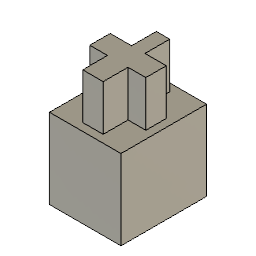
adapter_mitsumi_spacebar_to_cherry_stabilizer (Autodesk Fusion 360 design; units mm, degrees)
part number: 2025-08-30-15-09-30-402
Autodesk Fusion 360 part; units mm, degrees
note: some values were not read from the file. Set by a fixed rule: which face or edge a step refers to.
sketch "Mitsumi keycap interface" plane through (0, 0, 0) normal (0, 0, 1) x (1, 0, 0)
  line L0 (-0.48, 2.5) -> (0.48, 2.5)
  line L1 (0.48, 2.5) -> (0.48, 0.73)
  line L2 (-0.48, 0.7299) -> (-0.48, 2.5)
  line L3 (-2, 0.73) -> (2, 0.73)
  line L4 (2, 0.73) -> (2, -0.73)
  line L5 (2, -0.73) -> (-2, -0.73)
  line L6 (-2, -0.73) -> (-2, 0.73)
  line L7 (0.73, -0.73) -> (0.73, -2.5)
  line L8 (0.73, -2.5) -> (-0.73, -2.5)
  line L9 (-0.73, -2.5) -> (-0.73, -0.73)
  line L10 (0, 3.5) -> (0, -3.5) construction
  line L11 (-2.5, 0) -> (2.5, 0) construction
  dimension "d2" = 1.77
  dimension "d3" = 4
  dimension "d6" = 1.77
  dimension "d38" = 0.73
  dimension "d44" = 0.73
  dimension "d63" = 0.73
  dimension "d65" = 0.48
  dimension "d67" = 0.48
  dimension "d68" = 5
  dimension "d69" = 0.73
  constraint horizontal L3
  constraint coincident L5 L9.end
  constraint perpendicular L4 L5
  constraint coincident L5 L7.start
  constraint perpendicular L3 L4
  constraint perpendicular L0 L1
  constraint perpendicular L0 L2
  constraint perpendicular L7 L8
  constraint perpendicular L8 L9
  constraint perpendicular L1 L3
  measures "d2" distance of L0.end L1.end
  measures "d3" distance of L3.start L3.end
  measures "d6" distance of L7.start L7.end
  measures "d38" distance of L4.end L11
  measures "d44" distance of L7 L10
  measures "d63" distance of L3.start L11
  measures "d65" distance of L0.start L10
  measures "d67" distance of L0.end L10
  measures "d68" vertical distance of L0.end L7.end
  measures "d69" distance of L8.end L10
extrude "Extrude6" add sketch "Mitsumi keycap interface" along normal blind 3.25 makes body 1
sketch "Cherry stabilizer interface" plane through (0, 0, 0) normal (0, 0, 1) x (1, 0, 0)
  line L0 (-4, 0) -> (3, 0) construction
  line L1 (2.05, 0.66) -> (-2.05, 0.66)
  line L2 (-2.05, 0.66) -> (-2.05, -0.66)
  line L3 (-2.05, -0.66) -> (2.05, -0.66)
  line L4 (2.05, -0.66) -> (2.05, 0.66)
  line L5 (2.05, 0.66) -> (-2.05, -0.66) construction
  line L6 (-2.05, 0.66) -> (2.05, -0.66) construction
  line L7 (0.585, 2.05) -> (-0.585, 2.05)
  line L8 (-0.585, 2.05) -> (-0.585, -2.05)
  line L9 (-0.585, -2.05) -> (0.585, -2.05)
  line L10 (0.585, -2.05) -> (0.585, 2.05)
  line L11 (0.585, 2.05) -> (-0.585, -2.05) construction
  line L12 (-0.585, 2.05) -> (0.585, -2.05) construction
  line L13 (-2.15, 2.55) -> (2.15, 2.55)
  line L14 (2.15, 2.55) -> (2.15, -2.55)
  line L15 (2.15, -2.55) -> (-2.15, -2.55)
  line L16 (-2.15, -2.55) -> (-2.15, 2.55)
  line L17 (-2.15, 2.55) -> (2.15, -2.55) construction
  line L18 (2.15, 2.55) -> (-2.15, -2.55) construction
  dimension "d39" = 4.1
  dimension "d40" = 1.32
  dimension "d41" = 1.17
  dimension "d42" = 4.1
  dimension "d45" = 4.3
  dimension "d46" = 5.1
  constraint horizontal L1
  constraint perpendicular L1 L2
  constraint parallel L1 L3
  constraint parallel L2 L4
  constraint coincident L5 origin
  constraint coincident L6 origin
  constraint horizontal L7
  constraint perpendicular L7 L8
  constraint parallel L7 L9
  constraint parallel L8 L10
  constraint coincident L11 origin
  constraint coincident L12 origin
  constraint horizontal L13
  constraint perpendicular L13 L14
  constraint parallel L13 L15
  constraint parallel L14 L16
  constraint coincident L17 origin
  constraint coincident L18 origin
  measures "d39" distance of L2.end L3.end
  measures "d40" distance of L1.end L2.end
  measures "d41" distance of L8.end L9.end
  measures "d42" distance of L7.end L8.end
  measures "d45" distance of L14.end L15.end
  measures "d46" distance of L13.end L14.end
extrude "Extrude11" add sketch "Cherry stabilizer interface" against normal blind 3.6 separate body contours L1 L3 L4 L10 | L1 L3 L8 L10 | L1 L7 L8 L10 | L1 L2 L3 L8 | L3 L8 L9 L10 | L13 L14 L15 L16 makes body 2
extrude "Extrude12" add sketch "Cherry stabilizer interface" against normal blind 3.6 from surface at -3.6 separate body makes body 3
move_body "Move1" bodies 1 to x (1, 0, 0) y (0, 1, 0) z (0, 0, 1) at (0, 0, 1.5)
extrude "Extrude13" add 1 faces at (0.7167, -0.85, 0) along direction (0, 0, 1) blind 1.5 on bodies 2 bodies 1 2
extrude "Extrude14" cut 1 faces at (0.7167, -0.85, -3.6) along direction (0, 0, 1) blind 2 on bodies 1 bodies 1
move_body "Move2" bodies 3 to x (1, 0, 0) y (0, 1, 0) z (0, 0, 1) at (0, 0, 2)
move_body "Move3" bodies 3 to x (1, 0, 0) y (0, 1, 0) z (0, 0, 1) at (0, 0, -1)
move_face "MoveFace1" by (0, 0, 1) 1 faces at (0.7167, -0.85, -1.6) on bodies 1
move_body "Move4" bodies 3 to x (1, 0, 0) y (0, 1, 0) z (0, 0, 1) at (0, 0, 2)
move_face "MoveFace2" by (0.5, 0, 0) 3 faces at (2.15, 0.85, -1.8) (2.15, 0.85, -0.2) (2.15, 0.85, 0.5) on bodies 1 3
move_face "MoveFace3" by (-0.5, 0, 0) 3 faces at (-2.15, -0.85, -0.2) (-2.15, -0.85, 0.5) (-2.15, 0.85, -3) on bodies 1 3
move_face "MoveFace4" by (0.1, 0, 0) 3 faces at (-2.65, 0.85, -3) (-2.65, -0.85, -0.2) (-2.65, -0.85, 0.5) on bodies 1 3
move_face "MoveFace5" by (-0.1, 0, 0) 3 faces at (2.65, 0.85, -1.8) (2.65, 0.85, -0.2) (2.65, 0.85, 0.5) on bodies 1 3
extrude "Extrude15" add 3 faces at (0.85, -2.55, -0.2) (0.85, -2.55, 0.5) (-0.85, -2.55, -3) along direction (0, -1, 0) blind 0.5 on bodies 1 3 bodies 1 3
extrude "Extrude16" add 1 faces at (0.85, 2.55, -2.3) along direction (0, 1, 0) blind 0.5 on bodies 1 bodies 1
extrude "Extrude9" [suppressed]
extrude "Extrude10" [suppressed]
